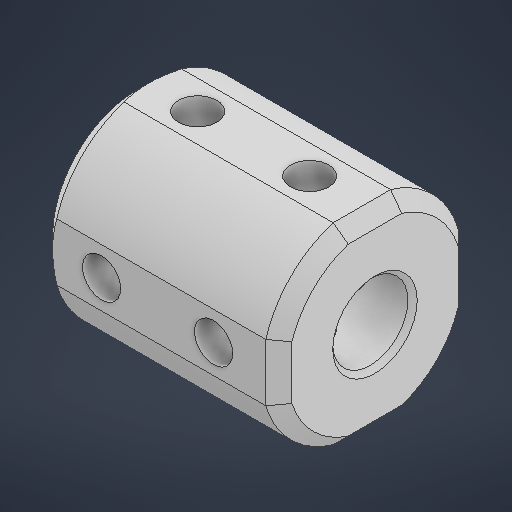
# Autodesk Inventor part: slipringMountArm
Saved by Autodesk Inventor 2027.1 (Build 311270010, 270A)
## iProperties
Created: 2026-10-10
Part Number: slipringMountArm
Material: Generic
Document SubType Name: Modeling
Designer: lucao
Density: 0.545229 g/cm^3
Appearance: Default
Mass: 3.48 g
Surface Area: 33.0392 cm^2
Volume: 6.38264 cm^3
Author: lucao
## iProperties of the stored document slipringMountArm_3DPrint.ipt
Created: 2026-10-13
Part Number: slipringMountArm_3DPrint
Material: Generic
Document SubType Name: Modeling
Designer: lucao
Density: 1 g/cm^3
Appearance: Default
Author: lucao
Autodesk Inventor part; units mm, degrees
ref_plane "YZ Plane" through (0, 0, 0) normal (1, 0, 0) x (0, 1, 0)
ref_plane "XZ Plane" through (0, 0, 0) normal (0, 1, 0) x (-1, 0, 0)
ref_plane "XY Plane" through (0, 0, 0) normal (0, 0, 1) x (1, 0, 0)
sketch "Sketch1" plane through (0, 0, 0) normal (1, 0, 0) x (0, 1, 0)
  circle A0 centre (0, 0) radius 6.025
  circle A1 centre (0, 0) radius 10.75
  dimension "d0" = 12.05
  dimension "d1" = 21.5
  constraints: 2 centre point, 2 coincident
  measures "d0" diameter of A0
  measures "d1" diameter of A1
extrude "Extrusion1" add sketch "Sketch1" along normal blind 10.5
chamfer "Chamfer1" distance 1.7 angle 45 1 edges at (0, -10.75, 0)
sketch "Sketch2" plane through (10.5, 0, 0) normal (1, 0, 0) x (0, 0, -1)
  circle A0 centre (0, 0) radius 10.75 projected
  circle A1 centre (0, 0) radius 6.025 projected
  circle A2 centre (0, 0) radius 4.025
  dimension "d7" = 8.05
  constraints: 1 centre point, 1 coincident
  measures "d7" diameter of A2
extrude "Extrusion2" add sketch "Sketch2" along normal blind 15 contours A0 | A1
sketch "Sketch3" plane through (25.5, 0, 0) normal (1, 0, 0) x (0, 0, -1)
  circle A0 centre (0, 0) radius 10.75 projected
  circle A1 centre (0, 0) radius 4.025 projected
  line L0 (-3.0777, 10.3) -> (3.0777, 10.3)
  circle A2 centre (0, 0) radius 10.75 projected
  point P0 (3.0777, 10.3)
  dimension "d10" = 10.3
  constraints: 2 end point, 1 horizontal, 1 point on circle, 2 other
  measures "d10" distance from line of point (0, 0) L0
extrude "Extrusion3" cut sketch "Sketch3" against normal through all contours L0 A0 picked at (-0.3463, 10.4332)
sketch "Sketch5" plane through (25.5, 10.3, 3.0777) normal (0, 1, 0) x (1, 0, 0)
  circle A0 centre (-19, 3.0777) radius 2.05
  circle A1 centre (-7, 3.0777) radius 2.05
  line L0 (0, 6.1555) -> (0, 0) projected
  point P0 (-25.5, 3.0777)
  point P1 (0, 3.0777)
  dimension "d13" = 4.1
  dimension "d14" = 4.1
  dimension "d15" = 7
  dimension "d16" = 6.5
  constraints: 2 centre point, 2 horizontal alignment, 1 midpoint
  measures "d13" diameter of A0
  measures "d14" diameter of A1
  measures "d15" distance from line of L0 A1.centre
  measures "d16" distance of point (-25.5, 3.078) A0.centre
extrude "Extrusion4" cut sketch "Sketch5" against normal up to surface (10.3 mm away)
pattern_circular "Circular Pattern1" count 4 over 360 about axis through (10.5, 0, 0) along (1, 0, 0) of "Extrusion4", "Extrusion3"
chamfer "Chamfer2" distance 1.4 angle 45 4 edges at (25.5, 10.3, 0) (25.5, 0, -10.3) (25.5, -10.3, 0) (25.5, 0, 10.3)
chamfer "Chamfer3" distance 1.4 angle 45 4 edges at (25.5, 7.6014, -7.6014) (25.5, 7.6014, 7.6014) (25.5, -7.6014, 7.6014) (25.5, -7.6014, -7.6014)
chamfer "Chamfer4" distance 0.5 angle 45 3 edges at (10.5, 0, 4.025) (0, -6.025, 0) (25.5, 0, 4.025)
body "Solid1"
